Autodesk Fusion 360 part; units mm, degrees
(part 2 of 3)
  line L909 (-36.6415, 53.4641) -> (-46.6415, 53.4641) construction
  line L910 (-45.8018, 69.3301) -> (-55.8018, 69.3301) construction
  line L911 (-45.8018, 69.3301) -> (-37.1415, 74.3301)
  line L912 (-9.6608, 26.7321) -> (-9.6608, 36.7321)
  line L913 (-26.9813, 26.7321) -> (-27.9813, 26.7321) construction
  line L914 (-36.1415, 42.5981) -> (-27.4813, 37.5981)
  line L915 (-27.9813, 36.7321) -> (-36.6415, 41.7321)
  line L916 (-18.321, 21.7321) -> (-9.6608, 26.7321) construction
  line L917 (-0.0005, 41.7321) -> (-8.6608, 36.7321)
  line L918 (-26.9813, 36.7321) -> (-27.4813, 37.5981) construction
  line L919 (-9.6608, 26.7321) -> (-8.6608, 26.7321) construction
  line L920 (-18.821, 20.866) -> (-27.4813, 25.866)
  line L921 (-8.6607, 26.7321) -> (-8.6607, 36.7321)
  line L922 (-86.603, -50) -> (-87.469, -50.5) construction
  line L923 (-86.603, -50) -> (-85.603, -50) construction
  line L924 (-0.0005, -100) -> (-0.8665, -100.5) construction
  line L925 (-86.603, -50) -> (-0.0005, -100) construction
  line L926 (-0.0005, -100) -> (-2.5005, -104.3301) construction
  line L927 (-2.5005, -104.3301) -> (-89.103, -54.3301) construction
  line L928 (-89.103, -54.3301) -> (-86.603, -50) construction
  line L929 (-86.603, -50) -> (-86.603, 50) construction
  line L930 (-86.603, 50) -> (-91.603, 50) construction
  line L931 (-91.603, 50) -> (-91.603, -50) construction
  line L932 (-91.603, -50) -> (-86.603, -50) construction
  line L933 (-91.603, -50) -> (-91.603, -54.7915) construction
  line L934 (-89.103, -54.3301) -> (-92.4535, -52.3957) construction
  line L935 (-0.0005, -100) -> (-0.0005, -108.6524) construction
  line L936 (-91.603, -52.8868) -> (-0.0005, -105.7735)
  line L937 (-0.0005, -105.7735) -> (91.6021, -52.8868)
  line L938 (91.6021, -52.8868) -> (91.6021, 52.8868)
  line L939 (91.6021, 52.8868) -> (-0.0005, 105.7735)
  line L940 (-0.0005, 105.7735) -> (-91.603, 52.8868)
  line L941 (-91.603, 52.8868) -> (-91.603, -52.8868)
  point P0 (-0.0005, 0)
  point P1 (-0.0004, 0)
  point P2 (9.1598, -15.866)
  point P3 (18.3201, 0)
  point P4 (27.4803, -15.866)
  point P5 (36.6406, 0)
  point P6 (18.3201, -31.7321)
  point P7 (54.9611, 0)
  point P8 (45.8009, -15.866)
  point P9 (36.6406, -31.7321)
  point P10 (-0.0004, -31.7321)
  point P11 (73.2816, 0)
  point P12 (64.1214, -15.866)
  point P13 (54.9611, -31.7321)
  point P14 (45.8009, -47.5981)
  point P15 (27.4803, -47.5981)
  point P16 (9.1598, -47.5981)
  point P17 (91.6021, 0)
  point P18 (82.4419, -15.866)
  point P19 (73.2816, -31.7321)
  point P20 (64.1214, -47.5981)
  point P21 (36.6406, -63.4641)
  point P22 (18.3201, -63.4641)
  point P23 (-0.0004, -63.4641)
  point P24 (82.4419, -47.5981)
  point P25 (91.6021, -31.7321)
  point P26 (73.2816, -63.4641)
  point P27 (54.9611, -63.4641)
  point P28 (45.8009, -79.3301)
  point P29 (27.4803, -79.3301)
  point P30 (9.1598, -79.3301)
  point P31 (18.3201, -95.1962)
  point P32 (-0.0004, -95.1962)
  point P33 (-9.1608, -79.3301)
  point P34 (-18.321, -63.4641)
  point P35 (-36.6415, 0)
  point P36 (-0.0005, -31.7321)
  point P37 (-36.6415, -63.4641)
  point P38 (-9.1608, -47.5981)
  point P39 (-0.0005, 0)
  point P40 (-18.321, 0)
  point P41 (-9.1608, -15.866)
  point P42 (-18.321, -95.1962)
  point P43 (-27.4813, -15.866)
  point P44 (-0.0005, 0)
  point P45 (-18.321, -31.7321)
  point P46 (-0.0005, -63.4641)
  point P47 (-36.6415, -31.7321)
  point P48 (-27.4813, -79.3301)
  point P49 (-82.4428, -47.5981)
  point P50 (-73.2825, -63.4641)
  point P51 (-64.1223, -47.5981)
  point P52 (-54.962, 0)
  point P53 (-64.1223, -15.866)
  point P54 (-45.8018, -47.5981)
  point P55 (-91.603, -31.7321)
  point P56 (-82.4428, -15.866)
  point P57 (-45.8018, -79.3301)
  point P58 (-54.962, -63.4641)
  point P59 (-45.8018, -15.866)
  point P60 (-91.603, 0)
  point P61 (-0.0009, 0)
  point P62 (-27.4813, -47.5981)
  point P63 (-73.2825, -31.7321)
  point P64 (-0.0005, -95.1962)
  point P65 (-54.962, -31.7321)
  point P66 (-0.0009, 0)
  point P67 (-0.0009, 0)
  point P68 (-0.0005, 0)
  point P69 (9.1598, 15.866)
  point P70 (-0.0005, 31.7321)
  point P71 (27.4803, 15.866)
  point P72 (36.6406, 31.7321)
  point P73 (-9.1608, 15.866)
  point P74 (-18.321, 31.7321)
  point P75 (-0.0004, 31.7321)
  point P76 (-0.0009, 0)
  point P77 (-0.0005, 0)
  point P78 (-0.0004, 0)
  point P79 (-0.0005, 0)
  point P80 (36.6406, 0)
  point P81 (18.3201, 0)
  point P82 (18.3201, 31.7321)
  point P83 (-18.321, 0)
  point P84 (-27.4813, 15.866)
  point P85 (54.9611, 31.7321)
  point P86 (45.8009, 47.5981)
  point P87 (45.8009, 15.866)
  point P88 (91.6021, 0)
  point P89 (91.6021, 31.7321)
  point P90 (54.9611, 63.4641)
  point P91 (82.4419, 47.5981)
  point P92 (45.8009, 79.3301)
  point P93 (73.2816, 63.4641)
  point P94 (54.9611, 0)
  point P95 (73.2816, 31.7321)
  point P96 (64.1214, 47.5981)
  point P97 (82.4419, 15.866)
  point P98 (73.2816, 0)
  point P99 (64.1214, 15.866)
  point P100 (-45.8018, 79.3301)
  point P101 (-73.2825, 63.4641)
  point P102 (-64.1223, 47.5981)
  point P103 (-82.4428, 47.5981)
  point P104 (-45.8018, 47.5981)
  point P105 (-36.6415, 63.4641)
  point P106 (-54.962, 63.4641)
  point P107 (-54.962, 31.7321)
  point P108 (-36.6415, 0)
  point P109 (27.4803, 47.5981)
  point P110 (18.3201, 63.4641)
  point P111 (9.1598, 47.5981)
  point P112 (-18.321, 63.4641)
  point P113 (-0.0005, 63.4641)
  point P114 (9.1598, 79.3301)
  point P115 (-27.4813, 47.5981)
  point P116 (-9.1608, 47.5981)
  point P117 (-64.1223, 15.866)
  point P118 (-54.962, 0)
  point P119 (-45.8018, 15.866)
  point P120 (-36.6415, 31.7321)
  point P121 (-73.2825, 31.7321)
  point P122 (-82.4428, 15.866)
  point P123 (-91.603, 0)
  point P124 (-91.603, 31.7321)
  point P125 (-27.4813, 79.3301)
  point P126 (-18.321, 95.1962)
  point P127 (-0.0004, 95.1962)
  point P128 (-0.0004, 63.4641)
  point P129 (36.6406, 63.4641)
  point P130 (27.4803, 79.3301)
  point P131 (-0.0005, 95.1962)
  point P132 (-9.1608, 79.3301)
  point P133 (18.3201, 95.1962)
  point P134 (-0.0005, 0)
  dimension "d1" = 86.603
  dimension "d2" = 50
  dimension "d3" = 90
  dimension "d4" = 100
  dimension "d5" = 8.6603
  dimension "d6" = 5
  dimension "d7" = 10
  dimension "d8" = 1
  dimension "d9" = 10
  dimension "d10" = 1
  dimension "d11" = 10
  dimension "d12" = 60
  dimension "d13" = 1
  dimension "d14" = 1
  dimension "d15" = 1
  dimension "d16" = 10
  dimension "d17" = 10
  dimension "d18" = 90
  dimension "d19" = 10
  dimension "d20" = 10
  dimension "d21" = 1
  dimension "d22" = 1
  dimension "d23" = 1
  dimension "d24" = 1
  dimension "d25" = 10
  dimension "d26" = 10
  dimension "d27" = 10
  dimension "d28" = 10
  dimension "d29" = 1
  dimension "d30" = 1
  dimension "d31" = 1
  dimension "d32" = 1
  dimension "d33" = 1
  dimension "d34" = 1
  dimension "d35" = 10
  dimension "d36" = 10
  dimension "d37" = 10
  dimension "d38" = 10
  dimension "d39" = 150
  dimension "d40" = 10
  dimension "d41" = 30
  dimension "d42" = 10
  dimension "d43" = 30
  dimension "d44" = 1
  dimension "d45" = 1
  dimension "d46" = 1
  dimension "d47" = 60
  dimension "d48" = 1
  dimension "d49" = 1
  dimension "d50" = 1
  dimension "d51" = 1
  dimension "d52" = 1
  dimension "d53" = 10
  dimension "d54" = 10
  dimension "d55" = 10
  dimension "d56" = 10
  dimension "d57" = 10
  dimension "d58" = 30
  dimension "d59" = 10
  dimension "d60" = 30
  dimension "d61" = 10
  dimension "d62" = 90
  dimension "d63" = 1
  dimension "d64" = 60
  dimension "d65" = 1
  dimension "d66" = 1
  dimension "d67" = 60
  dimension "d68" = 1
  dimension "d69" = 1
  dimension "d70" = 1
  dimension "d71" = 60
  dimension "d72" = 1
  dimension "d73" = 10
  dimension "d74" = 10
  dimension "d75" = 10
  dimension "d76" = 150
  dimension "d77" = 10
  dimension "d78" = 10
  dimension "d79" = 150
  dimension "d80" = 10
  dimension "d81" = 30
  dimension "d82" = 10
  dimension "d83" = 30
  dimension "d84" = 60
  dimension "d85" = 1
  dimension "d86" = 1
  dimension "d87" = 10
  dimension "d88" = 30
  dimension "d89" = 10
  dimension "d90" = 150
  dimension "d91" = 150
  dimension "d92" = 1
  dimension "d93" = 1
  constraint coincident L0.start L725.start
  constraint horizontal L0
  constraint coincident P134 P79
  constraint perpendicular L0 L8
  constraint perpendicular L8 L9
  constraint perpendicular L9 L10
  constraint perpendicular L15 L17
  constraint perpendicular L22 L24
  constraint perpendicular L16 L25
  constraint horizontal L33
  constraint perpendicular L27 L32
  constraint perpendicular L21 L34
  constraint perpendicular L28 L35
  constraint perpendicular L21 L36
  constraint perpendicular L20 L49
  constraint perpendicular L52 L57
  constraint perpendicular L55 L58
  constraint perpendicular L39 L59
  constraint perpendicular L45 L60
  constraint perpendicular L83 L85
  constraint perpendicular L54 L86
  constraint perpendicular L75 L87
  constraint perpendicular L76 L88
  constraint perpendicular L69 L89
  constraint perpendicular L63 L90
  constraint horizontal L115
  constraint horizontal L122
  constraint horizontal L129
  constraint perpendicular L126 L130
  constraint horizontal L131
  constraint perpendicular L126 L132
  constraint horizontal L134
  constraint perpendicular L113 L135
  constraint perpendicular L105 L136
  constraint perpendicular L99 L137
  constraint perpendicular L93 L138
  constraint horizontal L165
  constraint horizontal L172
  constraint horizontal L179
  constraint perpendicular L177 L180
  constraint horizontal L182
  constraint perpendicular L162 L183
  constraint perpendicular L155 L186
  constraint perpendicular L149 L187
  constraint horizontal L189
  constraint perpendicular L154 L188
  constraint horizontal L200
  constraint horizontal L209
  constraint horizontal L215
  constraint horizontal L222
  constraint horizontal L224
  constraint horizontal L225
  constraint horizontal L229
  constraint horizontal L234
  constraint coincident L4 L233.start
  constraint coincident L3 L232.end
  constraint coincident L4 L226.end
  constraint coincident L4 L227.start
  constraint coincident L4 L212.end
  constraint coincident L4 L207.end
  constraint coincident L4 L213.start
  constraint coincident L4 L202.start
  constraint coincident L4 L198.end
  constraint coincident L4 L201.end
  constraint coincident L4 L208.start
  constraint coincident L4 L199.start
  constraint coincident L4 L190.end
  constraint coincident L5 L191.start
  constraint coincident L5 L194.end
  constraint coincident L5 L195.start
  constraint coincident L5 L143.end
  constraint coincident L5 L139.end
  constraint coincident L5 L144.start
  constraint coincident L5 L140.start
  constraint symmetric L0.start L8 P76
  constraint symmetric L3.end L8 L4.start
  constraint symmetric L4.end L8 L2.end
  constraint symmetric P134 L8 P79
  constraint symmetric L8 P134 P79
  constraint symmetric L8 L9.end L338.start
  constraint symmetric L8 L10.end L262.end
  constraint symmetric L8 L11.end L344.end
  constraint symmetric L8 L12.end L258.start
  constraint symmetric L8 L13.end L258.end
  constraint symmetric L8 L14.end L357.start
  constraint symmetric L8 L15.end L262.start
  constraint symmetric L8 P78 P134
  constraint symmetric L8 L17.end L357.end
  constraint symmetric L8 L18.end L372.end
  constraint symmetric L8 L20.end L286.start
  constraint symmetric L8 L21.end L286.end
  constraint symmetric L8 L22.end L395.start
  constraint symmetric L8 P2 P41
  constraint symmetric L8 L24.end L289.start
  constraint symmetric L8 L26.end L288.start
  constraint symmetric L8 L27.end L288.end
  constraint symmetric L8 L28.end L322.end
  constraint symmetric L8 L29.end L425.start
  constraint symmetric L8 L30.end L323.start
  constraint symmetric L8 P81 P83
  constraint symmetric L8 L32.end L310.end
  constraint symmetric L8 L33.end L294.end
  constraint symmetric L8 L35.end L250.end
  constraint symmetric L8 L36.end L297.end
  constraint symmetric L8 L37.end L371.start
  constraint symmetric L8 L38.end L324.start
  constraint symmetric L8 L39.end L325.end
  constraint symmetric L8 L40.end L381.end
  constraint symmetric L8 P4 P43
  constraint symmetric L8 L43.end L319.start
  constraint symmetric L8 L44.end L319.end
  constraint symmetric L8 L45.end L337.end
  constraint symmetric L8 L46.end L419.end
  constraint symmetric L8 L47.end L250.start
  constraint symmetric L8 P80 P108
  constraint symmetric L8 L49.end L284.end
  constraint symmetric L8 L50.end L287.end
  constraint symmetric L8 L52.end L309.start
  constraint symmetric L8 L53.end L309.end
  constraint symmetric L8 L54.end L292.start
  constraint symmetric L8 L55.end L284.start
  constraint symmetric L8 P6 P45
  constraint symmetric L8 L58.end L314.end
  constraint symmetric L8 L59.end L324.end
  constraint symmetric L8 L60.end L328.end
  constraint symmetric L8 L61.end L342.start
  constraint symmetric L8 L62.end L330.start
  constraint symmetric L8 L63.end L330.end
  constraint symmetric L8 L64.end L434.end
  constraint symmetric L8 L65.end L333.start
  constraint symmetric L8 P94 P118
  constraint symmetric L8 L67.end L341.end
  constraint symmetric L8 L68.end L433.start
  constraint symmetric L8 L69.end L437.start
  constraint symmetric L8 L70.end L336.start
  constraint symmetric L8 L71.end L335.start
  constraint symmetric L8 P8 P59
  constraint symmetric L8 L73.end L363.start
  constraint symmetric L8 L74.end L349.start
  constraint symmetric L8 L75.end L349.end
  constraint symmetric L8 L76.end L339.start
  constraint symmetric L8 L77.end L339.end
  constraint symmetric L8 P9 P47
  constraint symmetric L8 L79.end L362.start
  constraint symmetric L8 L80.end L362.end
  constraint symmetric L8 L81.end L361.start
  constraint symmetric L8 L82.end L332.start
  constraint symmetric L8 L83.end L304.start
  constraint symmetric L8 P10 P36
  constraint symmetric L8 L85.end L304.end
  constraint symmetric L8 L86.end L285.start
  constraint symmetric L8 L87.end L238.start
  constraint symmetric L8 L88.end L351.end
  constraint symmetric L8 L89.end L329.end
  constraint symmetric L8 L90.end L263.end
  constraint symmetric L8 L92.end L318.start
  constraint symmetric L8 L93.end L318.end
  constraint symmetric L8 L94.end L420.start
  constraint symmetric L8 L95.end L263.start
  constraint symmetric L8 L97.end L331.end
  constraint symmetric L8 L98.end L429.start
  constraint symmetric L8 L100.end L326.end
  constraint symmetric L8 L101.end L329.start
  constraint symmetric L8 P12 P53
  constraint symmetric L8 L103.end L350.start
  constraint symmetric L8 L104.end L270.start
  constraint symmetric L8 L105.end L364.start
  constraint symmetric L8 L106.end L364.end
  constraint symmetric L8 L107.end L369.start
  constraint symmetric L8 P13 P65
  constraint symmetric L8 L109.end L238.end
  constraint symmetric L8 L110.end L235.end
  constraint symmetric L8 L111.end L253.start
  constraint symmetric L8 L112.end L236.start
  constraint symmetric L8 L113.end L243.end
  constraint symmetric L8 P14 P54
  constraint symmetric L8 L115.end L240.end
  constraint symmetric L8 L116.end L285.end
  constraint symmetric L8 L117.end L298.end
  constraint symmetric L8 L118.end L317.end
  constraint symmetric L8 L119.end L235.start
  constraint symmetric L8 L120.end L239.end
  constraint symmetric L8 P15 P62
  constraint symmetric L8 L122.end L383.end
  constraint symmetric L8 L123.end L456.start
  constraint symmetric L8 L124.end L428.start
  constraint symmetric L8 L125.end L312.start
  constraint symmetric L8 L126.end L311.start
  constraint symmetric L8 L127.end L306.start
  constraint symmetric L8 P16 P38
  constraint symmetric L8 L130.end L302.start
  constraint symmetric L8 L131.end L302.end
  constraint symmetric L8 L132.end L291.start
  constraint symmetric L8 L133.end L244.end
  constraint symmetric L8 L135.end L236.end
  constraint symmetric L8 L136.end L270.end
  constraint symmetric L8 L137.end L327.end
  constraint symmetric L8 L138.end L242.end
  constraint symmetric L8 L140.end L242.start
  constraint symmetric L8 P88 P123
  constraint symmetric L8 L142.end L343.end
  constraint symmetric L8 L144.end L320.end
  constraint symmetric L8 L145.end L321.end
  constraint symmetric L8 P18 P56
  constraint symmetric L8 L147.end L277.end
  constraint symmetric L8 L148.end L276.start
  constraint symmetric L8 L149.end L334.start
  constraint symmetric L8 L151.end L356.start
  constraint symmetric L8 P19 P63
  constraint symmetric L8 L153.end L279.start
  constraint symmetric L8 L154.end L264.start
  constraint symmetric L8 L155.end L264.end
  constraint symmetric L8 L156.end L273.end
  constraint symmetric L8 L157.end L257.start
  constraint symmetric L8 P20 P51
  constraint symmetric L8 L159.end L385.end
  constraint symmetric L8 L160.end L316.end
  constraint symmetric L8 L161.end L384.end
  constraint symmetric L8 L162.end L237.start
  constraint symmetric L8 L163.end L247.start
  constraint symmetric L8 P21 P37
  constraint symmetric L8 L165.end L252.end
  constraint symmetric L8 L167.end L307.end
  constraint symmetric L8 L168.end L387.start
  constraint symmetric L8 L169.end L290.start
  constraint symmetric L8 L170.end L290.end
  constraint symmetric L8 P22 P34
  constraint symmetric L8 L172.end L291.end
  constraint symmetric L8 L173.end L382.start
  constraint symmetric L8 L174.end L365.start
  constraint symmetric L8 L175.end L365.end
  constraint symmetric L8 L176.end L368.end
  constraint symmetric L8 L177.end L305.start
  constraint symmetric L8 P23 P46
  constraint symmetric L8 L179.end L388.end
  constraint symmetric L8 L180.end L296.end
  constraint symmetric L8 L181.end L293.start
  constraint symmetric L8 L183.end L237.end
  constraint symmetric L8 L184.end L249.end
  constraint symmetric L8 L186.end L266.end
  constraint symmetric L8 L187.end L267.start
  constraint symmetric L8 L188.end L269.start
  constraint symmetric L8 L191.end L268.end
  constraint symmetric L8 L192.end L278.start
  constraint symmetric L8 P24 P49
  constraint symmetric L8 L195.end L345.end
  constraint symmetric L8 P25 P55
  constraint symmetric L8 L197.end L269.end
  constraint symmetric L8 P26 P50
  constraint symmetric L8 L200.end L272.end
  constraint symmetric L8 L202.end L265.end
  constraint symmetric L8 L203.end L248.start
  constraint symmetric L8 L204.end L248.end
  constraint symmetric L8 P27 P58
  constraint symmetric L8 L206.end L246.start
  constraint symmetric L8 P28 P57
  constraint symmetric L8 L209.end L256.end
  constraint symmetric L8 L210.end L293.end
  constraint symmetric L8 L211.end L301.start
  constraint symmetric L8 L213.end L241.end
  constraint symmetric L8 P29 P48
  constraint symmetric L8 L215.end L378.end
  constraint symmetric L8 L216.end L374.start
  constraint symmetric L8 L217.end L374.end
  constraint symmetric L8 L218.end L407.start
  constraint symmetric L8 L219.end L405.start
  constraint symmetric L8 L220.end L296.start
  constraint symmetric L8 P30 P33
  constraint symmetric L8 L222.end L300.end
  constraint symmetric L8 L223.end L389.end
  constraint symmetric L8 L224.end L407.end
  constraint symmetric L8 L225.end L392.start
  constraint symmetric L8 L227.end L389.start
  constraint symmetric L8 P31 P42
  constraint symmetric L8 L229.end L409.end
  constraint symmetric L8 L230.end L370.start
  constraint symmetric L8 L231.end L370.end
  constraint symmetric L8 P32 P64
  constraint symmetric L8 L234.end L392.end
  constraint symmetric L8 L233.start L410.start
  constraint symmetric L8 L232.end L375.end
  constraint symmetric L8 L226.end L400.end
  constraint symmetric L8 L227.start L401.start
  constraint symmetric L8 L212.end L301.end
  constraint symmetric L8 L207.end L246.end
  constraint symmetric L8 L213.start L241.start
  constraint symmetric L8 L202.start L265.start
  constraint symmetric L8 L198.end L280.end
  constraint symmetric L8 L201.end L254.end
  constraint symmetric L8 L208.start L245.start
  constraint symmetric L8 L199.start L274.start
  constraint symmetric L8 L190.end L275.end
  constraint symmetric L8 L191.start L268.start
  constraint symmetric L8 L194.end L267.end
  constraint symmetric L8 L195.start L345.start
  constraint symmetric L8 L143.end L439.end
  constraint symmetric L8 L139.end L346.end
  constraint symmetric L8 L144.start L320.start
  constraint symmetric L8 L140.start L424.start
  constraint midpoint L5 L462.end
  constraint symmetric L0.start L462 L725.start
  constraint symmetric L0.end L462 L1.start
  constraint symmetric L2.end L462 L1.end
  constraint symmetric L3.end L462 L6.end
  constraint symmetric L4.end L462 L5.end
  constraint symmetric P134 L462 P79
  constraint symmetric L35.end L462 L47.end
  constraint symmetric L36.end L462 L546.end
  constraint symmetric L37.end L462 L589.end
  constraint symmetric L38.end L462 L470.start
  constraint symmetric L45.end L462 L44.end
  constraint symmetric L46.end L462 L43.end
  constraint symmetric L47.end L462 L35.end
  constraint symmetric P80 L462 P5
  constraint symmetric L49.end L462 L544.start
  constraint horizontal L923
  constraint parallel L4 L924
  constraint perpendicular L925 L926
  constraint parallel L925 L927
  constraint parallel L926 L928
  constraint parallel L423 L925
  constraint perpendicular L929 L930
  constraint parallel L929 L931
  constraint parallel L930 L932
  constraint perpendicular L923 L929
  constraint perpendicular L932 L933
  constraint perpendicular L928 L934
  constraint vertical L935
  constraint coincident L935 L936.end
  constraint coincident L933 L936.start
  constraint coincident L934 L936.start
  measures "d1" distance of L0.start L0.end
  measures "d2" distance of L0.end L1.end
  measures "d3" angle of L0 L1
  measures "d4" distance of L1.end L2.end
  measures "d5" distance of P134 L9.end
  measures "d6" distance of L9.end L10.end
  measures "d7" distance of L10.end L15.end
  measures "d8" distance of L14.end L17.end
  measures "d9" distance of L17.end L18.end
  measures "d10" distance of L22.end L24.end
  measures "d11" distance of L24.end L30.end
  measures "d12" angle of L32 L33
  measures "d13" distance of L26.end L32.end
  measures "d14" distance of L27.end L35.end
  measures "d15" distance of L20.end L36.end
  measures "d16" distance of L36.end L32.end
  measures "d17" distance of L35.end L47.end L845
  measures "d18" angle of L49 L50
  measures "d19" distance of L49.end L50.end
  measures "d20" distance of L49.end L50.end
  measures "d21" distance of L50.end L57.end
  measures "d22" distance of L55.end L58.end
  measures "d23" distance of L38.end L59.end
  measures "d24" distance of L44.end L60.end
  measures "d25" distance of L60.end L65.end
  measures "d26" distance of L59.end L71.end
  measures "d27" distance of L58.end L73.end
  measures "d28" distance of L57.end L83.end
  measures "d29" distance of L83.end L85.end
  measures "d30" distance of L54.end L86.end
  measures "d31" distance of L75.end L87.end
  measures "d32" distance of L75.end L88.end
  measures "d33" distance of L68.end L89.end
  measures "d34" distance of L62.end L90.end
  measures "d35" distance of L90.end L95.end
  measures "d36" distance of L89.end L101.end
  measures "d37" distance of L88.end L107.end
  measures "d38" distance of L87.end L109.end
  measures "d39" angle of L109 L115
  measures "d40" distance of L86.end L120.end
  measures "d41" angle of L121 L122
  measures "d42" distance of L85.end L127.end
  measures "d43" angle of L128 L129
  measures "d44" distance of L125.end L130.end
  measures "d45" distance of L130.end L131.end
  measures "d46" distance of L126.end L132.end
  measures "d47" angle of L133 L134
  measures "d48" distance of L119.end L133.end
  measures "d49" distance of L112.end L135.end
  measures "d50" distance of L104.end L136.end
  measures "d51" distance of L98.end L137.end
  measures "d52" distance of L92.end L138.end
  measures "d53" distance of L138.end L140.end
  measures "d54" distance of L137.end L145.end
  measures "d55" distance of L136.end L151.end
  measures "d56" distance of L135.end L157.end
  measures "d57" distance of L133.end L163.end
  measures "d58" angle of L164 L165
  measures "d59" distance of L132.end L170.end
  measures "d60" angle of L171 L172
  measures "d61" distance of L131.end L177.end
  measures "d62" angle of L178 L179
  measures "d63" distance of L177.end L180.end
  measures "d64" angle of L181 L182
  measures "d65" distance of L169.end L181.end
  measures "d66" distance of L162.end L183.end
  measures "d67" angle of L183 L184
  measures "d68" distance of L183.end L184.end
  measures "d69" distance of L154.end L186.end
  measures "d70" distance of L148.end L187.end
  measures "d71" angle of L188 L189
  measures "d72" distance of L154.end L188.end
  measures "d73" distance of L186.end L192.end
  measures "d74" distance of L187.end L195.end
  measures "d75" distance of L188.end L197.end
  measures "d76" angle of L197 L200
  measures "d77" distance of L184.end L204.end
  measures "d78" distance of L183.end L206.end
  measures "d79" angle of L206 L209
  measures "d80" distance of L181.end L213.end
  measures "d81" angle of L214 L215
  measures "d82" distance of L180.end L220.end
  measures "d83" angle of L221 L222
  measures "d84" angle of L223 L224
  measures "d85" distance of L218.end L223.end
  measures "d86" distance of L223.end L225.end
  measures "d87" distance of L223.end L227.end
  measures "d88" angle of L228 L229
  measures "d89" distance of L225.end L230.end
  measures "d90" angle of L230 L234
  measures "d91" angle of L922 L923
  measures "d92" distance of L2.end L922.end
  measures "d93" distance of L3.end L924.end
extrude "Extrude1" add sketch "Sketch1" along normal blind 10 contours L2 L3 L4 L5 L6 L7 L139 L140 L141 L142 L143 L144 L145 L146 L190 L191 L192 L193 L194 L195 L196 L197 L198 L199 L201 L202 L203 L204 L205 L206 L207 L208 L210 L211 L212 L213 L214 L226 L227 L228 L230 L231 L232 L233 L241 L242 L245 L246 L248 L249 L254 L265 L267 L268 L269 L274 L275 L278 L280 L282 L293 L301 L320 L321 L327 L343 L345 L346 L347 L353 L359 L370 L375 L380 L389 L400 L401 L410 L414 L423 L424 L426 L439 L464 L465 L466 L475 L480 L485 L488 L489 L503 L515 L521 L524 L529 L533 L535 L542 L580 L581 L598 L600 L603 L604 L607 L611 L617 L619 L629 L631 L639 L648 L655 L657 L658 L662 L687 L688 L689 L690 L695 L703 L710 L716 L756 L759 L761 L764 L778 L785 L794 L796 L801 L816 L822 L824 L830 L833 L835 L836 L839 L843 L844 L845 L847 L849 L853 L865 L871 L875 L878 L881 L883 L884 L885 L886 L900 L902 L903 L908 L911
extrude "Extrude2" add sketch "Sketch1" along normal blind 10 contours L936 L937 L938 L939 L940 L941
sketch "Sketch2" plane through (0, 0, 0) normal (0, 1, 0) x (1, 0, 0)
  line L0 (0, -18.541) -> (0, -50) construction
  line L1 (1, -100) -> (-1, -100)
  line L2 (-89.0903, -29.9987) -> (-89.7083, -28.0966)
  line L3 (-1, -0.3249) -> (-0.9935, -0.3228)
  line L4 (-89.7083, -28.0966) -> (-19.6025, -5.3178)
  line L5 (-18.9847, -7.22) -> (-89.0903, -29.9987)
  line L6 (-1, -100) -> (-1, -20.2866)
  line L7 (1, -20.2866) -> (1, -100)
  line L8 (0, -21.0132) -> (0.5883, -20.5857)
  line L9 (0.6385, -18.0772) -> (0.5883, -20.5857) construction
  line L10 (0, -50) -> (-1, -100) construction
  line L11 (-0.9401, -2.9952) -> (1, -100) construction
  line L12 (-1, -17.8145) -> (-1, -3.0777)
  line L13 (-52.0917, 73.3993) -> (-53.7097, 72.2237)
  line L14 (-53.7097, 72.2237) -> (-12.7333, 15.8245)
  line L15 (-0.8539, 2.8765) -> (-9.6621, 15)
  line L16 (-11.1152, 17) -> (-52.0917, 73.3993)
  line L17 (-17.2516, -4.554) -> (-3.2361, 0)
  line L18 (-11.2801, 13.8244) -> (-2.618, 1.9021)
  line L19 (1, -3.0778) -> (1, -17.8145)
  line L20 (1, -0.3249) -> (0.9935, -0.3228)
  line L21 (0.9935, -0.3228) -> (1, -0.3249) construction
  line L22 (90.0382, -29.2552) -> (90.3504, -29.3566) construction
  line L23 (0.9935, -0.3228) -> (1, -0.3249) construction
  line L24 (3.2361, 0) -> (17.2515, -4.5539)
  line L25 (31.6972, 45.3288) -> (11.1152, 17)
  line L26 (9.6621, 15) -> (1, 3.0777)
  line L27 (-16.6336, -6.456) -> (-8.8168, -12.1352) construction
  line L28 (1, -17.8145) -> (8.8167, -12.1353) construction
  line L29 (1, -1.3764) -> (1, -1.3764) construction
  line L30 (17.2515, -4.5539) -> (14.5749, 3.6842) construction
  line L31 (0, 0) -> (0, 1.0515) construction
  line L32 (-52.0917, -73.3993) -> (-53.7097, -72.2237)
  line L33 (85.2865, 28.7614) -> (90.0418, 30.3064)
  line L34 (90.0418, 30.3064) -> (89.4237, 32.2085)
  line L35 (-0.309, 0.9511) -> (-0.3089, 0.9507)
  line L36 (-16.6336, -6.456) -> (-9.6258, -11.5474)
  line L37 (-8.0078, -12.723) -> (-1, -17.8145)
  line L38 (-18.9847, -7.22) -> (-10.8014, -13.1655)
  line L39 (-9.1833, -14.3411) -> (-1, -20.2866)
  line L40 (-53.7097, -72.2237) -> (-10.8014, -13.1655)
  line L41 (-9.1833, -14.3411) -> (-52.0917, -73.3993)
  line L42 (-9.6258, -11.5474) -> (-2.6181, -1.9021)
  line L43 (-0.9401, -2.9952) -> (-8.0078, -12.723)
  line L44 (-0.309, 0.9511) -> (0, 1.0515)
  line L45 (17.2515, -4.5539) -> (14.5749, 3.6842)
  line L46 (13.339, 7.488) -> (11.2802, 13.8245)
  line L47 (2.618, 1.9021) -> (13.9569, 5.5861)
  line L48 (15.859, 6.2041) -> (85.2865, 28.7614)
  line L49 (19.6027, -5.3179) -> (16.477, 4.3022)
  line L50 (-0.8539, 2.8765) -> (-0.9269, 2.8528)
  line L51 (4.6176, 4.6543) -> (11.2802, 13.8245)
  line L52 (-0.9727, -1.3675) -> (-1, -1.3764)
  line L53 (-2.6181, -1.9021) -> (-16.6336, -6.456)
  line L54 (0, 0) -> (0, 0)
  line L55 (53.7102, -72.2234) -> (52.0922, -73.3989)
  line L56 (16.6335, -6.456) -> (2.618, -1.9021)
  line L57 (1, -1.3764) -> (0.9726, -1.3675)
  line L58 (1, -3.0778) -> (8.0078, -12.723)
  line L59 (9.1834, -14.341) -> (52.0922, -73.3989)
  line L60 (1, -20.2866) -> (9.1834, -14.341)
  line L61 (10.8014, -13.1655) -> (18.9847, -7.22)
  line L62 (2.618, -1.9021) -> (9.6258, -11.5474)
  line L63 (10.8014, -13.1655) -> (53.7102, -72.2234)
  line L64 (0.6385, -18.0772) -> (8.0078, -12.723)
  line L65 (9.6258, -11.5474) -> (16.6335, -6.456)
  line L66 (1, 100) -> (-1, 100)
  line L67 (0, 0) -> (0.309, 0.9511)
  line L68 (-90.0418, 30.3064) -> (-90.6598, 28.4043)
  line L69 (-11.2801, 13.8244) -> (-13.9569, 5.5861)
  line L70 (-14.5749, 3.684) -> (-17.2516, -4.554)
  line L71 (-90.6598, 28.4043) -> (-16.477, 4.302)
  line L72 (-14.5749, 3.684) -> (-3.2361, 0)
  line L73 (-12.7333, 15.8245) -> (-15.859, 6.2041)
  line L74 (-16.477, 4.302) -> (-19.6025, -5.3178)
  line L75 (-15.859, 6.2041) -> (-90.0418, 30.3064)
  line L76 (11.1152, 17) -> (1, 17)
  line L77 (-1, 17) -> (-11.1152, 17)
  line L78 (-1, 100) -> (-1, 17)
  line L79 (9.6621, 15) -> (1, 15)
  line L80 (-1, 15) -> (-9.6621, 15)
  line L81 (1, 3.0777) -> (1, 15)
  line L82 (1, 17) -> (1, 100)
  line L83 (-1, 15) -> (-1, 3.0776)
  line L84 (0.309, 0.9511) -> (0, 1.0515)
  line L85 (-2.618, 1.9021) -> (-13.9569, 5.5861)
  line L86 (11.1152, 17) -> (52.2601, 73.6312)
  line L87 (52.2601, 73.6312) -> (53.8781, 72.4556)
  line L88 (16.477, 4.3022) -> (19.6027, -5.3179)
  line L89 (17.6067, 0.8254) -> (16.477, 4.3022)
  line L90 (15.241, 8.1061) -> (12.7332, 15.8244)
  line L91 (53.8781, 72.4556) -> (12.7332, 15.8244)
  line L92 (1, -0.3249) -> (0.9775, -0.3559)
  line L93 (11.2802, 13.8245) -> (4.6176, 4.6543)
  line L94 (9.6621, 15) -> (1, 3.0777)
  line L95 (0, 1.7013) -> (-0.8608, 0.5166)
  line L96 (6.1696, 3.056) -> (2.618, 1.9021)
  line L97 (0, 1.0515) -> (-0.618, 0.8507)
  line L98 (60.8645, -18.7246) -> (90.3472, -28.3041)
  line L99 (90.3472, -28.3041) -> (89.7292, -30.2062)
  line L100 (89.7292, -30.2062) -> (80.0223, -27.0523)
  line L101 (12.7332, 15.8244) -> (15.859, 6.2041)
  line L102 (0.0002, 0) -> (0, -0.0001)
  line L103 (0, 0) -> (-0.0546, -0.168)
  line L104 (0, 0) -> (0, -0.0001)
  line L105 (0, 0) -> (1, 0) construction
  line L106 (90.6594, 28.4056) -> (90.0414, 30.3077)
  line L107 (4.6176, 4.6543) -> (2.618, 1.9021)
  line L108 (0, 1.0515) -> (-0.309, 0.9511)
  line L109 (13.339, 7.488) -> (14.0284, 5.366)
  line L110 (3.2361, 0) -> (14.5749, 3.6842)
  line L111 (16.477, 4.3022) -> (90.6594, 28.4056)
  line L112 (90.0414, 30.3077) -> (15.8589, 6.2043)
  line L113 (13.9568, 5.5863) -> (2.618, 1.9021)
  line L114 (19.6027, -5.3179) -> (90.3472, -28.3041)
  line L115 (90.3472, -28.3041) -> (89.7292, -30.2062)
  line L116 (89.7292, -30.2062) -> (18.9847, -7.22)
  point P0 (0, -50)
  dimension "d100" = 17
  dimension "d101" = 50
  dimension "d102" = 2
  dimension "d103" = 95
  dimension "d111" = 2
  dimension "d113" = 90
  dimension "d118" = 2
  dimension "d119" = 90
  dimension "d120" = 90
  dimension "d141" = 9.662
  dimension "d142" = 9.662
  dimension "d150" = 2
  dimension "d151" = 90
  dimension "d158" = 5
  dimension "d159" = 2
  dimension "d161" = 95
  dimension "d167" = 2
  dimension "d178" = 2
  dimension "d179" = 90
  dimension "d183" = 70
  dimension "d188" = 2
  dimension "d191" = 72
  dimension "d196" = 90
  constraint coincident L31.start L54.start
  constraint vertical L0
  constraint coincident P0 L9
  constraint coincident P0 L0.end
  constraint parallel L21 L23
  constraint coincident L3.start L6
  constraint coincident L17.start L4
  constraint collinear L4 L17
  constraint coincident L12.start L36
  constraint collinear L6 L12
  constraint coincident L19.end L64
  constraint coincident L7.start L8
  constraint collinear L8 L60
  constraint collinear L9 L10
  constraint coincident L18.start L14
  constraint coincident L16.start L15
  constraint collinear L14 L18
  constraint collinear L15 L16
  constraint collinear L21 L22
  constraint coincident L49.start L24
  constraint coincident L26.start L25
  constraint collinear L25 L26
  constraint parallel L27 L36
  constraint parallel L28 L64
  constraint parallel L30 L45
  constraint vertical L31
  constraint perpendicular L33 L45
  constraint perpendicular L33 L34
  constraint coincident L36.end L40
  constraint collinear L36 L37
  constraint collinear L38 L39
  constraint collinear L40 L42
  constraint coincident L42.end L52
  constraint collinear L44 L47
  constraint coincident L90.start L49
  constraint coincident L46.start L45
  constraint collinear L45 L46
  constraint collinear L47 L48
  constraint collinear L49 L88
  constraint collinear L52 L53
  constraint coincident L43 L12.end
  constraint perpendicular L55 L58
  constraint coincident L29.start L56
  constraint coincident L19 L29.start
  constraint collinear L56 L57
  constraint collinear L58 L59
  constraint coincident L61.start L62
  constraint collinear L60 L61
  constraint coincident L62.end L64
  constraint collinear L62 L63
  constraint collinear L64 L65
  constraint vertical L81
  constraint perpendicular L66 L81
  constraint perpendicular L66 L78
  constraint perpendicular L73 L84
  constraint perpendicular L68 L84
  constraint coincident L70.start L71
  constraint collinear L69 L70
  constraint coincident L71.end L73
  constraint collinear L71 L72
  constraint coincident L73.end L84
  constraint collinear L73 L74
  constraint collinear L75 L84
  constraint coincident L76.end L81
  constraint collinear L76 L77
  constraint coincident L80.start L79
  constraint collinear L78 L83
  constraint collinear L79 L80
  constraint collinear L81 L82
  constraint coincident L15 L83.end
  constraint coincident L18.end L84
  constraint collinear L84 L85
  constraint parallel L26 L94
  constraint perpendicular L86 L87
  constraint coincident L88 L89.start
  constraint collinear L89 L90
  constraint collinear L91 L93
  constraint collinear L92 L93
  constraint collinear L94 L95
  constraint coincident L47 L96.start
  constraint coincident L95 L97.end
  constraint parallel L44 L96
  constraint collinear L96 L97
  constraint perpendicular L22 L99
  constraint coincident L99 L22.start
  constraint parallel L49 L101
  constraint perpendicular L45 L102
  constraint horizontal L105
  constraint coincident L107 L47.start
  constraint collinear L108 L112
  constraint coincident L105 L102.start
  constraint parallel L45 L109
  constraint coincident L49.end L110
  constraint collinear L110 L111
  constraint coincident L101 L112.end
  constraint coincident L109 L113.start
  constraint collinear L112 L113
  measures "d100" distance of L31.start L76
  measures "d101" distance of L31.start L0.end
  measures "d102" distance of L1.start L1.end
  measures "d103" distance of L31.start L22.end
  measures "d111" distance of L2.start L2.end
  measures "d113" angle of L2 L4
  measures "d118" distance of L13.start L13.end
  measures "d119" angle of L13 L15
  measures "d120" angle of L13 L14
  measures "d141" distance of L27.start L27.end
  measures "d142" distance of L19.end L28.end
  measures "d150" distance of L32.start L32.end
  measures "d151" angle of L32 L40
  measures "d158" distance of L33.start L33.end
  measures "d159" distance of L33.end L34.end
  measures "d161" distance of L34.end L50.end
  measures "d167" distance of L55.start L55.end
  measures "d178" distance of L68.start L68.end
  measures "d179" angle of L68 L71
  measures "d183" distance of L25.end L86.end
  measures "d188" distance of L98.end L99.end
  measures "d191" angle of L104 L105
  measures "d196" angle of L106 L110
extrude "Extrude3" add sketch "Sketch2" along normal blind 2